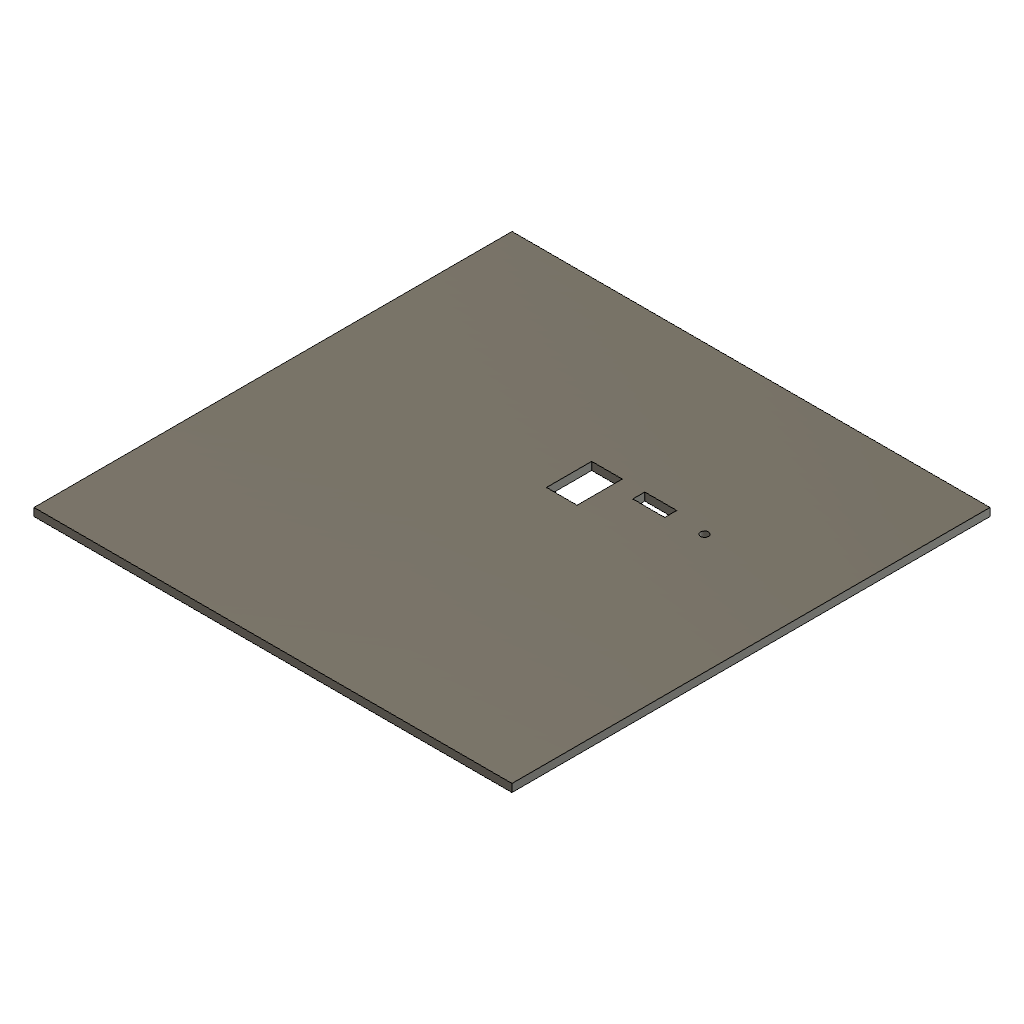
Robo Soccer(TOP) (Autodesk Fusion 360 design; units mm, degrees)
part number: 2026-11-05-16-06-45-779
Autodesk Fusion 360 part; units mm, degrees
sketch "Sketch1" plane through (0, 0, 0) normal (0, 1, 0) x (1, 0, 0)
  line L0 (-90, 90) -> (90, 90)
  line L1 (90, 90) -> (90, -90)
  line L2 (90, -90) -> (-90, -90)
  line L3 (-90, -90) -> (-90, 90)
  line L4 (20, 30) -> (32, 30)
  line L5 (32, 30) -> (32, 25.5)
  line L6 (32, 25.5) -> (20, 25.5)
  line L7 (20, 25.5) -> (20, 30)
  circle A0 centre (45, 27.5) radius 1.5
  line L8 (0, 30) -> (11.5, 30)
  line L9 (11.5, 30) -> (11.5, 13)
  line L10 (11.5, 13) -> (0, 13)
  line L11 (0, 13) -> (0, 30)
  dimension "d1" = 180
  dimension "d2" = 180
  dimension "d3" = 12
  dimension "d4" = 4.5
  dimension "d5" = 3
  dimension "d6" = 11.5
  dimension "d7" = 17
  constraint horizontal L0
  constraint vertical L1
  constraint horizontal L2
  constraint vertical L3
  constraint horizontal L4
  constraint vertical L5
  constraint horizontal L6
  constraint vertical L7
  constraint horizontal L8
  constraint vertical L9
  constraint horizontal L10
  constraint vertical L11
  measures "d1" distance of L0.start L0.end
  measures "d2" distance of L0.start L2.end
  measures "d3" distance of L4.start L4.end
  measures "d4" distance of L4.start L6.end
  measures "d5" diameter of A0
  measures "d6" distance of L8.start L8.end
  measures "d7" distance of L8.start L10.end
extrude "Extrude1" add sketch "Sketch1" along normal blind 3
